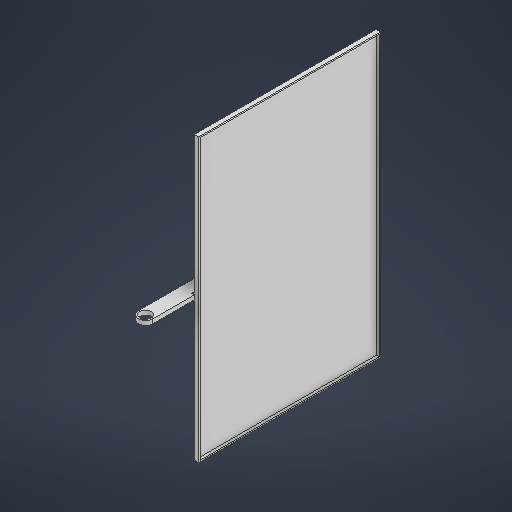
# Autodesk Inventor part: panel_link
Saved by Autodesk Inventor 2027.1 (Build 311270010, 270A)
## iProperties
Created: 2026-11-04
Part Number: panel_link
Material: Ogólny
Document SubType Name: Modeling
Designer: User
Density: 1 g/cm^3
Appearance: Domyślna
Author: User
Autodesk Inventor part; units mm, degrees
ref_plane "YZ Plane" through (0, 0, 0) normal (1, 0, 0) x (0, 1, 0)
ref_plane "XZ Plane" through (0, 0, 0) normal (0, 1, 0) x (-1, 0, 0)
sketch "Szkic1" plane through (0, 0, 0) normal (0, 1, 0) x (-1, 0, 0)
  circle A0 centre (0, 0) radius 4
  circle A1 centre (0, 0) radius 5
  line L0 (5, 0) -> (5, -100)
  line L1 (5, 0) -> (105, 0) construction
  line L2 (0, -5) -> (0, -7.6605) construction
  line L3 (5, -100) -> (-9.8353, -100) construction
  line L4 (5, -100) -> (19.8353, -100) construction
  line L5 (-5, 0) -> (-5, -100)
  line L6 (5, -200) -> (5, -100)
  line L7 (-5, -200) -> (-5, -100)
  line L8 (-5, -200) -> (5, -200)
  line L9 (0, 0) -> (0, -80) construction
  line L10 (0, 0) -> (80, 0) construction
  circle A2 centre (0, -80) radius 4
  dimension "d0" = 8
  dimension "d1" = 10
  dimension "d2" = 100
  dimension "d3" = 90
  dimension "d4" = 180
  dimension "d5" = 80
  dimension "d6" = 90
  dimension "d7" = 8
  constraints: 22 end point, 4 symmetric about line, 3 centre point, 3 coincident, 3 equal length, 3 horizontal, 3 vertical, 2 point on circle, 1 tangent
  measures "d0" diameter of A0
  measures "d1" diameter of A1
  measures "d2" distance of L0.start L0.end
  measures "d3" angle of L0 L1
  measures "d4" angle of L3 L4
  measures "d5" distance of L9.start L9.end
  measures "d6" angle of L9 L10
  measures "d7" diameter of A2
extrude "Wyciągnięcie proste1" add sketch "Szkic1" along normal blind 3
ref_plane "Płaszczyzna konstrukcyjna1" through (5, 0, 0) normal (1, 0, 0) x (0, 0, -1)
sketch "Szkic3" plane through (5, 0, 0) normal (1, 0, 0) x (0, 0, -1)
  line L0 (0, 0) -> (200, 0) projected
  line L1 (200, 0) -> (200, 3) projected
  line L2 (0, 3) -> (200, 3) projected
  line L3 (0, 0) -> (0, 3) projected
  line L4 (200, 0) -> (200, 3) projected
  line L5 (156, -97) -> (156, 100)
  line L6 (156, 100) -> (29, 100)
  line L7 (29, 100) -> (29, -97)
  line L8 (29, -97) -> (156, -97)
  line L9 (156, -97) -> (29, 100) construction
  line L10 (156, 100) -> (29, -97) construction
  line L11 (0, 0) -> (-5, 0) projected
  line L12 (-5, 0) -> (-5, 3)
  dimension "d21" = 197
  dimension "d22" = 127
  dimension "d28" = 44
  dimension "d29" = 97
  dimension "d30" = 0
  dimension "d31" = 0
  dimension "d32" = 0
  dimension "d33" = 3
  dimension "d34" = 0
  constraints: 14 end point, 3 parallel, 1 perpendicular, 1 vertical
  measures "d21" distance of L7.end L6.end
  measures "d22" distance of L6.end L5.end
  measures "d28" distance between parallel lines of L1 L5
  measures "d29" distance between parallel lines of L2 L6
  measures "d30" distance from line of point (200, 3) L1
  measures "d31" distance from line of point (200, 3) L2
  measures "d32" distance from line of point (200, 0) L1
  measures "d33" distance from line of point (200, 0) L2
  measures "d34" distance from line of L12.end L2
extrude "Wyciągnięcie proste3" add sketch "Szkic3" along normal blind 3 contours L7 L2 L5 L0 | L0 L5 L8 L7 | L7 L6 L5 L2
shell "Skorupa1" thickness 1 removed faces 1 at (8, 34.3333, -71.3333)
offset faces "Rozmiar1" outward -50 faces at (1.6667, 1, -200)
offset faces "Rozmiar2" outward 1.25 faces at (-1.3333, 2, -36.6667)
fillet "Zaokrąglenie1" radius 2 2 edges at (5, 0, -89.5) (5, 3, -89.5)
